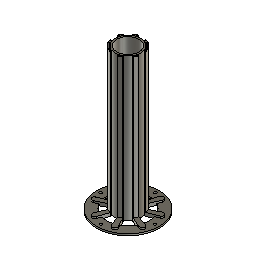
LAMP CORE (Autodesk Fusion 360 design; units mm, degrees)
part number: 2026-05-21-09-26-11-656
Autodesk Fusion 360 part; units mm, degrees
sketch "Sketch1" plane through (0, 0, 0) normal (0, 0, 1) x (1, 0, 0)
  circle A0 centre (0, 0) radius 36.6
  circle A1 centre (0, 0) radius 25
  dimension "d1" = 73.2
  dimension "d2" = 50
  constraint coincident A0.centre A1.centre
  constraint concentric A0 A1
  measures "d1" diameter of A0
  measures "d2" diameter of A1
extrude "Extrude1" add sketch "Sketch1" along normal blind 2 makes body 1
sketch "Sketch2" plane through (0, 0, 0) normal (0, 0, 1) x (1, 0, 0)
  circle A0 centre (0, 0) radius 15
  circle A1 centre (0, 0) radius 13
  dimension "d5" = 30
  dimension "d6" = 26
  constraint coincident A0.centre A1.centre
  constraint concentric A0 A1
  measures "d5" diameter of A0
  measures "d6" diameter of A1
extrude "Extrude2" add sketch "Sketch2" along normal blind 168 separate body makes body 2
sketch "Sketch3" plane through (0, 0, 168) normal (0, 0, 1) x (-1, 0, 0)
  circle A0 centre (0, 0) radius 13
  circle A1 centre (0, 0) radius 15
  line L0 (6.4849, 13.5258) -> (6.9618, 14.6269)
  line L1 (4.978, 14.1499) -> (5.3635, 15.2863)
  line L2 (5.3635, 15.2863) -> (3.943, 15.7682)
  line L3 (6.9618, 14.6269) -> (8.3382, 14.0307)
  line L4 (8.3382, 14.0307) -> (8.7357, 14.9483)
  line L5 (3.943, 15.7682) -> (4.2642, 16.7152)
  arc A2 (8.7357, 14.9483) -> (4.2642, 16.7152) centre (0.2494, 0.0129) ccw
  line L6 (-6.4855, 13.5255) -> (-7.0165, 14.6016)
  line L7 (-7.0165, 14.6016) -> (-8.3616, 13.9379)
  line L8 (-8.3616, 13.9379) -> (-8.8041, 14.8347)
  arc A3 (-4.393, 16.7471) -> (-8.8041, 14.8347) centre (0.1672, 0.1855) ccw
  line L9 (-4.0252, 15.8172) -> (-4.393, 16.7471)
  line L10 (-5.42, 15.2655) -> (-4.0252, 15.8172)
  line L11 (-4.9787, 14.1497) -> (-5.42, 15.2655)
  line L12 (-14.1499, 4.978) -> (-15.2863, 5.3635)
  line L13 (-15.2863, 5.3635) -> (-15.7682, 3.943)
  line L14 (-15.7682, 3.943) -> (-16.7152, 4.2642)
  arc A4 (-14.9483, 8.7357) -> (-16.7152, 4.2642) centre (-0.0129, 0.2494) ccw
  line L15 (-14.0307, 8.3382) -> (-14.9483, 8.7357)
  line L16 (-14.6269, 6.9618) -> (-14.0307, 8.3382)
  line L17 (-13.5258, 6.4849) -> (-14.6269, 6.9618)
  line L18 (-13.5255, -6.4855) -> (-14.6016, -7.0165)
  line L19 (-14.6016, -7.0165) -> (-13.9379, -8.3616)
  line L20 (-13.9379, -8.3616) -> (-14.8347, -8.8041)
  arc A5 (-16.7471, -4.393) -> (-14.8347, -8.8041) centre (-0.1855, 0.1672) ccw
  line L21 (-15.8172, -4.0252) -> (-16.7471, -4.393)
  line L22 (-15.2655, -5.42) -> (-15.8172, -4.0252)
  line L23 (-14.1497, -4.9787) -> (-15.2655, -5.42)
  line L24 (-4.978, -14.1499) -> (-5.3635, -15.2863)
  line L25 (-5.3635, -15.2863) -> (-3.943, -15.7682)
  line L26 (-3.943, -15.7682) -> (-4.2642, -16.7152)
  arc A6 (-8.7357, -14.9483) -> (-4.2642, -16.7152) centre (-0.2494, -0.0129) ccw
  line L27 (-8.3382, -14.0307) -> (-8.7357, -14.9483)
  line L28 (-6.9618, -14.6269) -> (-8.3382, -14.0307)
  line L29 (-6.4849, -13.5258) -> (-6.9618, -14.6269)
  line L30 (6.4855, -13.5255) -> (7.0165, -14.6016)
  line L31 (7.0165, -14.6016) -> (8.3616, -13.9379)
  line L32 (8.3616, -13.9379) -> (8.8041, -14.8347)
  arc A7 (4.393, -16.7471) -> (8.8041, -14.8347) centre (-0.1672, -0.1855) ccw
  line L33 (4.0252, -15.8172) -> (4.393, -16.7471)
  line L34 (5.42, -15.2655) -> (4.0252, -15.8172)
  line L35 (4.9787, -14.1497) -> (5.42, -15.2655)
  line L36 (14.1499, -4.978) -> (15.2863, -5.3635)
  line L37 (15.2863, -5.3635) -> (15.7682, -3.943)
  line L38 (15.7682, -3.943) -> (16.7152, -4.2642)
  arc A8 (14.9483, -8.7357) -> (16.7152, -4.2642) centre (0.0129, -0.2494) ccw
  line L39 (14.0307, -8.3382) -> (14.9483, -8.7357)
  line L40 (14.6269, -6.9618) -> (14.0307, -8.3382)
  line L41 (13.5258, -6.4849) -> (14.6269, -6.9618)
  line L42 (13.5255, 6.4855) -> (14.6016, 7.0165)
  line L43 (14.6016, 7.0165) -> (13.9379, 8.3616)
  line L44 (13.9379, 8.3616) -> (14.8347, 8.8041)
  arc A9 (16.7471, 4.393) -> (14.8347, 8.8041) centre (0.1855, -0.1672) ccw
  line L45 (15.8172, 4.0252) -> (16.7471, 4.393)
  line L46 (15.2655, 5.42) -> (15.8172, 4.0252)
  line L47 (14.1497, 4.9787) -> (15.2655, 5.42)
  dimension "d9" = 1.729
  dimension "d10" = 4.978
  dimension "d11" = 1.2
  dimension "d12" = 1.2
  dimension "d13" = 1.5
  dimension "d14" = 1.5
  dimension "d15" = 3.943
  dimension "d16" = 1
  dimension "d17" = 1
  dimension "d18" = 17.178
  dimension "d19" = 1.631
  dimension "d21" = 360
  constraint coincident A1 L0.start
  constraint coincident A1 L1.start
  constraint perpendicular L1 L2
  constraint perpendicular L0 L3
  constraint perpendicular L3 L4
  constraint perpendicular L2 L5
  measures "d9" distance of L0.end L1.end
  measures "d10" horizontal distance of A0.centre L1.start
  measures "d11" distance of L1.start L1.end
  measures "d12" distance of L0.start L0.end
  measures "d13" distance of L1.end L2.end
  measures "d14" distance of L0.end L3.end
  measures "d15" horizontal distance of A0.centre L2.end
  measures "d16" distance of L2.end L5.end
  measures "d17" distance of L3.end L4.end
  measures "d18" radius of A2
  measures "d19" distance of L0.start L1.start
extrude "Extrude3" add sketch "Sketch3" against normal blind 168 contours A1 L42 L43 L44 A9 L45 L46 L47 | A1 L36 L37 L38 A8 L39 L40 L41 | A1 L0 L1 L2 L3 L4 L5 A2 | A1 L30 L31 L32 A7 L33 L34 L35 | A1 L6 L7 L8 A3 L9 L10 L11 | A1 L24 L25 L26 A6 L27 L28 L29 | A1 L12 L13 L14 A4 L15 L16 L17 | A1 L18 L19 L20 A5 L21 L22 L23 bodies 2
sketch "Sketch4" plane through (0, 0, 0) normal (0, 0, 1) x (1, 0, 0)
  circle A0 centre (0, 0) radius 13
  arc A1 (-4.978, -14.1499) -> (4.9787, -14.1497) centre (0, 0) ccw
  line L0 (4.9787, -14.1497) -> (5.42, -15.2655)
  line L1 (5.42, -15.2655) -> (4.0252, -15.8172)
  line L2 (4.0252, -15.8172) -> (4.393, -16.7471)
  arc A2 (4.393, -16.7471) -> (8.8041, -14.8347) centre (-0.1672, -0.1855) ccw
  line L3 (8.8041, -14.8347) -> (8.3616, -13.9379)
  line L4 (8.3616, -13.9379) -> (7.0165, -14.6016)
  line L5 (7.0165, -14.6016) -> (6.4855, -13.5255)
  arc A3 (6.4855, -13.5255) -> (13.5258, -6.4849) centre (0, 0) ccw
  line L6 (13.5258, -6.4849) -> (14.6269, -6.9618)
  line L7 (14.6269, -6.9618) -> (14.0307, -8.3382)
  line L8 (14.0307, -8.3382) -> (14.9483, -8.7357)
  arc A4 (14.9483, -8.7357) -> (16.7152, -4.2642) centre (0.0129, -0.2494) ccw
  line L9 (16.7152, -4.2642) -> (15.7682, -3.943)
  line L10 (15.7682, -3.943) -> (15.2863, -5.3635)
  line L11 (15.2863, -5.3635) -> (14.1499, -4.978)
  arc A5 (14.1499, -4.978) -> (14.1497, 4.9787) centre (0, 0) ccw
  line L12 (14.1497, 4.9787) -> (15.2655, 5.42)
  line L13 (15.2655, 5.42) -> (15.8172, 4.0252)
  line L14 (15.8172, 4.0252) -> (16.7471, 4.393)
  arc A6 (16.7471, 4.393) -> (14.8347, 8.8041) centre (0.1855, -0.1672) ccw
  line L15 (14.8347, 8.8041) -> (13.9379, 8.3616)
  line L16 (13.9379, 8.3616) -> (14.6016, 7.0165)
  line L17 (14.6016, 7.0165) -> (13.5255, 6.4855)
  arc A7 (13.5255, 6.4855) -> (6.4849, 13.5258) centre (0, 0) ccw
  line L18 (6.4849, 13.5258) -> (6.9618, 14.6269)
  line L19 (6.9618, 14.6269) -> (8.3382, 14.0307)
  line L20 (8.3382, 14.0307) -> (8.7357, 14.9483)
  arc A8 (8.7357, 14.9483) -> (4.2642, 16.7152) centre (0.2494, 0.0129) ccw
  line L21 (4.2642, 16.7152) -> (3.943, 15.7682)
  line L22 (3.943, 15.7682) -> (5.3635, 15.2863)
  line L23 (5.3635, 15.2863) -> (4.978, 14.1499)
  arc A9 (4.978, 14.1499) -> (-4.9787, 14.1497) centre (0, 0) ccw
  line L24 (-4.9787, 14.1497) -> (-5.42, 15.2655)
  line L25 (-5.42, 15.2655) -> (-4.0252, 15.8172)
  line L26 (-4.0252, 15.8172) -> (-4.393, 16.7471)
  arc A10 (-4.393, 16.7471) -> (-8.8041, 14.8347) centre (0.1672, 0.1855) ccw
  line L27 (-8.8041, 14.8347) -> (-8.3616, 13.9379)
  line L28 (-8.3616, 13.9379) -> (-7.0165, 14.6016)
  line L29 (-7.0165, 14.6016) -> (-6.4855, 13.5255)
  arc A11 (-6.4855, 13.5255) -> (-13.5258, 6.4849) centre (0, 0) ccw
  line L30 (-13.5258, 6.4849) -> (-14.6269, 6.9618)
  line L31 (-14.6269, 6.9618) -> (-14.0307, 8.3382)
  line L32 (-14.0307, 8.3382) -> (-14.9483, 8.7357)
  arc A12 (-14.9483, 8.7357) -> (-16.7152, 4.2642) centre (-0.0129, 0.2494) ccw
  line L33 (-16.7152, 4.2642) -> (-15.7682, 3.943)
  line L34 (-15.7682, 3.943) -> (-15.2863, 5.3635)
  line L35 (-15.2863, 5.3635) -> (-14.1499, 4.978)
  arc A13 (-14.1499, 4.978) -> (-14.1497, -4.9787) centre (0, 0) ccw
  line L36 (-14.1497, -4.9787) -> (-15.2655, -5.42)
  line L37 (-15.2655, -5.42) -> (-15.8172, -4.0252)
  line L38 (-15.8172, -4.0252) -> (-16.7471, -4.393)
  arc A14 (-16.7471, -4.393) -> (-14.8347, -8.8041) centre (-0.1855, 0.1672) ccw
  line L39 (-14.8347, -8.8041) -> (-13.9379, -8.3616)
  line L40 (-13.9379, -8.3616) -> (-14.6016, -7.0165)
  line L41 (-14.6016, -7.0165) -> (-13.5255, -6.4855)
  arc A15 (-13.5255, -6.4855) -> (-6.4849, -13.5258) centre (0, 0) ccw
  line L42 (-6.4849, -13.5258) -> (-6.9618, -14.6269)
  line L43 (-6.9618, -14.6269) -> (-8.3382, -14.0307)
  line L44 (-8.3382, -14.0307) -> (-8.7357, -14.9483)
  arc A16 (-8.7357, -14.9483) -> (-4.2642, -16.7152) centre (-0.2494, -0.0129) ccw
  line L45 (-4.2642, -16.7152) -> (-3.943, -15.7682)
  line L46 (-3.943, -15.7682) -> (-5.3635, -15.2863)
  line L47 (-5.3635, -15.2863) -> (-4.978, -14.1499)
  line L48 (14.8347, 8.8041) -> (26.2662, 14.5848)
  line L49 (16.7471, 4.393) -> (28.6592, 9.1045)
  arc A17 (28.6592, 9.1045) -> (26.2662, 14.5848) centre (27.4627, 11.8446) ccw
  line L50 (14.8347, 8.8041) -> (13.9379, 8.3616)
  line L51 (14.8347, 8.8041) -> (13.9379, 8.3616)
  line L52 (15.8172, 4.0252) -> (16.7471, 4.393)
  line L53 (13.9379, 8.3616) -> (15.8172, 4.0252)
  line L54 (8.7357, 14.9483) -> (13.8273, 26.703)
  arc A18 (13.8273, 26.703) -> (8.26, 28.886) centre (11.0437, 27.7945) ccw
  line L55 (4.2642, 16.7152) -> (8.26, 28.886)
  line L56 (4.2642, 16.7152) -> (3.943, 15.7682)
  line L57 (3.943, 15.7682) -> (8.3382, 14.0307)
  line L58 (8.3382, 14.0307) -> (8.7357, 14.9483)
  line L59 (-4.393, 16.7471) -> (-9.1045, 28.6592)
  arc A19 (-9.1045, 28.6592) -> (-14.5848, 26.2662) centre (-11.8446, 27.4627) ccw
  line L60 (-8.8041, 14.8347) -> (-14.5848, 26.2662)
  line L61 (-8.8041, 14.8347) -> (-8.3616, 13.9379)
  line L62 (-8.3616, 13.9379) -> (-4.0252, 15.8172)
  line L63 (-4.0252, 15.8172) -> (-4.393, 16.7471)
  line L64 (-14.9483, 8.7357) -> (-26.703, 13.8273)
  arc A20 (-26.703, 13.8273) -> (-28.886, 8.26) centre (-27.7945, 11.0437) ccw
  line L65 (-16.7152, 4.2642) -> (-28.886, 8.26)
  line L66 (-16.7152, 4.2642) -> (-15.7682, 3.943)
  line L67 (-15.7682, 3.943) -> (-14.0307, 8.3382)
  line L68 (-14.0307, 8.3382) -> (-14.9483, 8.7357)
  line L69 (-16.7471, -4.393) -> (-28.6592, -9.1045)
  arc A21 (-28.6592, -9.1045) -> (-26.2662, -14.5848) centre (-27.4627, -11.8446) ccw
  line L70 (-14.8347, -8.8041) -> (-26.2662, -14.5848)
  line L71 (-14.8347, -8.8041) -> (-13.9379, -8.3616)
  line L72 (-13.9379, -8.3616) -> (-15.8172, -4.0252)
  line L73 (-15.8172, -4.0252) -> (-16.7471, -4.393)
  line L74 (-8.7357, -14.9483) -> (-13.8273, -26.703)
  arc A22 (-13.8273, -26.703) -> (-8.26, -28.886) centre (-11.0437, -27.7945) ccw
  line L75 (-4.2642, -16.7152) -> (-8.26, -28.886)
  line L76 (-4.2642, -16.7152) -> (-3.943, -15.7682)
  line L77 (-3.943, -15.7682) -> (-8.3382, -14.0307)
  line L78 (-8.3382, -14.0307) -> (-8.7357, -14.9483)
  line L79 (4.393, -16.7471) -> (9.1045, -28.6592)
  arc A23 (9.1045, -28.6592) -> (14.5848, -26.2662) centre (11.8446, -27.4627) ccw
  line L80 (8.8041, -14.8347) -> (14.5848, -26.2662)
  line L81 (8.8041, -14.8347) -> (8.3616, -13.9379)
  line L82 (8.3616, -13.9379) -> (4.0252, -15.8172)
  line L83 (4.0252, -15.8172) -> (4.393, -16.7471)
  line L84 (14.9483, -8.7357) -> (26.703, -13.8273)
  arc A24 (26.703, -13.8273) -> (28.886, -8.26) centre (27.7945, -11.0437) ccw
  line L85 (16.7152, -4.2642) -> (28.886, -8.26)
  line L86 (16.7152, -4.2642) -> (15.7682, -3.943)
  line L87 (15.7682, -3.943) -> (14.0307, -8.3382)
  line L88 (14.0307, -8.3382) -> (14.9483, -8.7357)
  dimension "d24" = 5.98
  dimension "d25" = 12.81
  dimension "d27" = 2.99
  dimension "d28" = 12.81
  dimension "d30" = 360
  constraint coincident A6.end L15.start
  constraint coincident L14.end A6.start
  constraint perpendicular L13 L49
  constraint coincident L15.end L16.start
  constraint coincident L13.end L14.start
  measures "d24" distance of L48.end L49.end
  measures "d25" distance of L14.end L49.end
  measures "d27" radius of A17
  measures "d28" distance of A6.end L48.end
extrude "Extrude4" add sketch "Sketch4" along normal blind 4 contours L42 L43 L44 A16 L45 L46 L47 L76 L77 L78 | L0 L1 L2 A2 L3 L4 L5 L81 L82 L83 | A16 L74 A22 L75 | A2 L79 A23 L80 | L36 L37 L38 A14 L39 L40 L41 L71 L72 L73 | L6 L7 L8 A4 L9 L10 L11 L86 L87 L88 | A14 L69 A21 L70 | A4 L84 A24 L85 | L30 L31 L32 A12 L33 L34 L35 L66 L67 L68 | L12 L13 L14 A6 L15 L16 L17 L50 L51 L52 L53 | A12 L64 A20 L65 | A6 L48 L49 A17 | L24 L25 L26 A10 L27 L28 L29 L61 L62 L63 | L18 L19 L20 A8 L21 L22 L23 L56 L57 L58 | A10 L59 A19 L60 | A8 L54 A18 L55 bodies 1 2
sketch "Sketch5" plane through (0, 0, 2) normal (0, 0, 1) x (-1, 0, 0)
  line L0 (9.1045, -28.6592) -> (7.2341, -23.9305)
  arc A0 (-6.6853, -24.0896) -> (7.2341, -23.9305) centre (0, 0) ccw
  line L1 (-6.6853, -24.0896) -> (-8.26, -28.886)
  arc A1 (-13.8273, -26.703) -> (-8.26, -28.886) centre (-11.0437, -27.7945) ccw
  line L2 (-13.8273, -26.703) -> (-11.8061, -22.0367)
  arc A2 (-21.7611, -12.3067) -> (-11.8061, -22.0367) centre (0, 0) ccw
  line L3 (-21.7611, -12.3067) -> (-26.2662, -14.5848)
  arc A3 (-28.6592, -9.1045) -> (-26.2662, -14.5848) centre (-27.4627, -11.8446) ccw
  line L4 (-28.6592, -9.1045) -> (-23.9305, -7.2341)
  arc A4 (-24.0896, 6.6853) -> (-23.9305, -7.2341) centre (0, 0) ccw
  line L5 (-24.0896, 6.6853) -> (-28.886, 8.26)
  arc A5 (-26.703, 13.8273) -> (-28.886, 8.26) centre (-27.7945, 11.0437) ccw
  line L6 (-26.703, 13.8273) -> (-22.0367, 11.8061)
  arc A6 (-12.3067, 21.7611) -> (-22.0367, 11.8061) centre (0, 0) ccw
  line L7 (-12.3067, 21.7611) -> (-14.5848, 26.2662)
  arc A7 (-9.1045, 28.6592) -> (-14.5848, 26.2662) centre (-11.8446, 27.4627) ccw
  line L8 (-9.1045, 28.6592) -> (-7.2341, 23.9305)
  arc A8 (6.6853, 24.0896) -> (-7.2341, 23.9305) centre (0, 0) ccw
  line L9 (6.6853, 24.0896) -> (8.26, 28.886)
  arc A9 (13.8273, 26.703) -> (8.26, 28.886) centre (11.0437, 27.7945) ccw
  line L10 (13.8273, 26.703) -> (11.8061, 22.0367)
  arc A10 (21.7611, 12.3067) -> (11.8061, 22.0367) centre (0, 0) ccw
  line L11 (21.7611, 12.3067) -> (26.2662, 14.5848)
  arc A11 (28.6592, 9.1045) -> (26.2662, 14.5848) centre (27.4627, 11.8446) ccw
  line L12 (28.6592, 9.1045) -> (23.9305, 7.2341)
  arc A12 (24.0896, -6.6853) -> (23.9305, 7.2341) centre (0, 0) ccw
  line L13 (24.0896, -6.6853) -> (28.886, -8.26)
  arc A13 (26.703, -13.8273) -> (28.886, -8.26) centre (27.7945, -11.0437) ccw
  line L14 (26.703, -13.8273) -> (22.0367, -11.8061)
  arc A14 (12.3067, -21.7611) -> (22.0367, -11.8061) centre (0, 0) ccw
  line L15 (12.3067, -21.7611) -> (14.5848, -26.2662)
  arc A15 (9.1045, -28.6592) -> (14.5848, -26.2662) centre (11.8446, -27.4627) ccw
  circle A16 centre (0, 0) radius 36.6
  circle A17 centre (0, -32) radius 1.6
  circle A18 centre (32, 0) radius 1.6
  circle A19 centre (0, 32) radius 1.6
  circle A20 centre (-32, 0) radius 1.6
  dimension "d33" = 3.2
  dimension "d34" = 32
  dimension "d36" = 360
  constraint vertical A0.centre A17.centre
  measures "d33" diameter of A17
  measures "d34" vertical distance of A0.centre A17.centre
extrude "Extrude5" cut sketch "Sketch5" against normal through all contours A17 | A18 | A19 | A20 bodies 1
